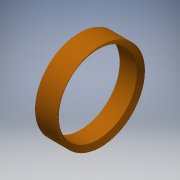
# Autodesk Inventor part: 15-0012-0307
Saved by Autodesk Inventor 2016 SP2 (Build 200236200, 236)
## iProperties
Created: 2017-10-23
Part Number: 15-0012-0307
Material: Plastic (PEEK)
Document SubType Name: Modeling
Designer: jellerm1
Density: 1.32 g/cm^3
Appearance: Orange
Project: Quantum Gas Microscope
Cost Center: 15-0012
User Status: Work in Progress
Authority: Georgios Siviloglou
RuleStatus: InUse
Category: IOP
Company: Universiteit van Amsterdam
BeforeDocSave0: Open Form
Author: jellerm1
Title: Quantum Gas Microscope
Revision Number: A
Autodesk Inventor part; units mm, degrees
ref_plane "YZ Plane" through (0, 0, 0) normal (1, 0, 0) x (0, 1, 0)
ref_plane "XZ Plane" through (0, 0, 0) normal (0, 1, 0) x (-1, 0, 0)
ref_plane "XY Plane" through (0, 0, 0) normal (0, 0, 1) x (1, 0, 0)
sketch "Sketch1" plane through (0, 0, 0) normal (0, 0, 1) x (1, 0, 0)
  line L0 (0, 125.258) -> (0, -125.258) construction
  line L1 (-231.2137, 0) -> (154.7383, 0) construction
  line L2 (0, 22.5) -> (9.4465, 22.5)
  line L3 (9.4465, 22.5) -> (11.1222, 25.4)
  line L4 (11.1222, 25.4) -> (-0.8057, 25.4)
  line L5 (-0.8057, 25.4) -> (0, 22.5)
  line L6 (0, 0) -> (27.5804, 0)
  circle A0 centre (51.7323, 0) radius 47.87 construction
  line L7 (-1.3905, 23.95) -> (10.2843, 23.95) construction
  circle A1 centre (-86.6077, 0) radius 89.47 construction
  line L8 (19.7122, 23.95) -> (-0.4028, 23.95) construction
  dimension "d4" = 95.74
  dimension "d8" = 178.94
  dimension "d0" = 50.8
  dimension "d1" = 45
  dimension "d3" = 0
  dimension "d6" = 1.45
  dimension "d9" = 138.34
  constraints: 14 end point, 3 point on line, 2 midpoint, 1 horizontal, 1 parallel, 1 perpendicular, 8 other
  measures "d0" diameter of L4 L6
  measures "d1" diameter of L2 L6
  measures "d3" distance from line of L0 L2.start
  measures "d6" distance between parallel lines of L7 L2
  measures "d9" distance of point (51.732, 0) point (-86.608, 0)
revolve "Revolution1" add sketch "Sketch1" angle 360 about axis through (0, 0, 0) along (1, 0, 0)
body "Solid1"
